Tool Slot Holster V6 (Autodesk Fusion 360 design; units mm, degrees)
part number: 2025-11-12-18-28-41-438
part number: 2025-11-12-18-30-06-467
Autodesk Fusion 360 part; units mm, degrees
sketch "Sketch1" plane through (0, 0, 0) normal (0, 0, 1) x (1, 0, 0) in component "Holster"
  line L0 (25.25, 25.25) -> (-25.25, 25.25)
  line L1 (-25.25, 25.25) -> (-25.25, -25.25)
  line L2 (-25.25, -25.25) -> (25.25, -25.25)
  line L3 (25.25, -25.25) -> (25.25, 25.25)
  line L4 (25.25, 25.25) -> (-25.25, -25.25) construction
  line L5 (-25.25, 25.25) -> (25.25, -25.25) construction
  line L6 (15.25, 15.25) -> (-15.25, 15.25)
  line L7 (-15.25, 15.25) -> (-15.25, -15.25)
  line L8 (-15.25, -15.25) -> (15.25, -15.25)
  line L9 (15.25, -15.25) -> (15.25, 15.25)
  line L10 (15.25, 15.25) -> (-15.25, -15.25) construction
  line L11 (-15.25, 15.25) -> (15.25, -15.25) construction
  dimension "d4" = 10
  dimension "d5" = 30.5
  constraint horizontal L0
  constraint perpendicular L0 L1
  constraint parallel L0 L2
  constraint parallel L1 L3
  constraint coincident L4 origin
  constraint coincident L5 origin
  constraint perpendicular L6 L7
  constraint parallel L6 L8
  constraint parallel L7 L9
  constraint coincident L10 origin
  constraint coincident L11 origin
  constraint coincident L4 L6.start
  constraint equal L7 L8
  measures "d4" distance of L3 L9
  measures "d5" distance of L7.end L8.end
extrude "Extrude1" add sketch "Sketch1" along normal blind 80 in component "Holster"
extrude "Extrude2" add sketch "Sketch1" along normal blind 10 from surface at 25 contours L6 L7 L8 L9 in component "Holster"
sketch "Sketch2" plane through (0, 0, 35) normal (0, 0, 1) x (-1, 0, 0) in component "Holster"
  line L0 (-15.25, 15.25) -> (-15.25, -15.25)
  line L1 (-15.25, -15.25) -> (15.25, -15.25)
  line L2 (15.25, -15.25) -> (15.25, 15.25)
  line L3 (15.25, 15.25) -> (-15.25, 15.25)
  line L4 (-10, -10) -> (10, -10)
  line L5 (10, -10) -> (10, 10)
  line L6 (10, 10) -> (-10, 10)
  line L7 (-10, 10) -> (-10, -10)
  line L8 (-10, -10) -> (10, 10) construction
  line L9 (10, -10) -> (-10, 10) construction
  dimension "d11" = 5.25
  constraint horizontal L4
  constraint perpendicular L4 L5
  constraint parallel L4 L6
  constraint parallel L5 L7
  constraint coincident L8 origin
  constraint coincident L9 origin
  constraint equal L5 L6
  measures "d11" distance of L2 L5
extrude "Extrude3" cut sketch "Sketch2" along normal mid plane 40 contours L4 L5 L6 L7 in component "Holster"
chamfer "Chamfer1" distance 6 angle 45 4 edges at (-15.25, 0, 80) (15.25, 0, 80) (0, 15.25, 80) (0, -15.25, 80) tangent chain off in component "Holster"
fillet "Fillet1" radius 2 4 edges at (25.25, 0, 80) (0, 25.25, 80) (-25.25, 0, 80) (0, -25.25, 80) in component "Holster"
fillet "Fillet1" radius 2 4 edges at (-25.25, -25.25, 40) (25.25, -25.25, 40) (25.25, 25.25, 40) (-25.25, 25.25, 40) in component "Holster"
fillet "Fillet1" radius 2 12 edges at (-15.25, -15.25, 54.5) (-15.25, 15.25, 54.5) (15.25, 15.25, 54.5) (15.25, -15.25, 54.5) (10, 10, 30) (-10, 10, 30) (10, -10, 30) (-10, -10, 30) (15.25, -15.25, 12.5) (15.25, 15.25, 12.5) (-15.25, 15.25, 12.5) (-15.25, -15.25, 12.5) in component "Holster"
component "Holster" placed x (1, 0, 0) y (0, 1, 0) z (0, 0, 1) at (0, 0, 0)
